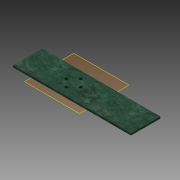
# Autodesk Inventor part: Pitch_Back
Saved by Autodesk Inventor 2013 (Build 170138000, 138)
## iProperties
Created: 2013-09-30
Part Number: Pitch_Back
Material: Generic
Document SubType Name: Modeling
Designer: Jeff
Density: 1 g/cm^3
Author: Jeff
Autodesk Inventor part; units mm, degrees
ref_plane "YZ Plane" through (0, 0, 0) normal (1, 0, 0) x (0, 1, 0)
ref_plane "XZ Plane" through (0, 0, 0) normal (0, 1, 0) x (-1, 0, 0)
ref_plane "XY Plane" through (0, 0, 0) normal (0, 0, 1) x (1, 0, 0)
ref_plane "Work Plane1" through (0, 0, 0) normal (0, 0, 1) x (1, 0, 0)
sketch "Sketch1" plane through (0, 0, 0) normal (0, 0, 1) x (1, 0, 0)
  line L0 (-37.5, -12.1467) -> (37.5, -12.1467)
  line L1 (37.5, 11.8533) -> (-37.5, 11.8533)
  line L2 (-37.5, 11.8533) -> (-37.5, -12.1467)
  line L3 (0, 0) -> (19.2852, -0.1467)
  line L4 (0, 0) -> (0, 8.1446)
  circle A0 centre (6, 0) radius 1.25
  circle A1 centre (0, 6) radius 1.25
  circle A2 centre (-6, 0) radius 1.25
  circle A3 centre (0, -6) radius 1.25
  line L5 (59.3125, -12.1467) -> (59.3125, 11.8533) projected
  line L6 (37.5, 11.8533) -> (59.3125, 11.8533)
  line L7 (59.3125, -12.1467) -> (37.5, -12.1467)
  point P0 (0, 0)
  point P1 (-37.5, 11.8533)
  dimension "d2" = 2.5
  dimension "d3" = 6
  dimension "d6" = 360
  dimension "d10" = 24
  constraints: 14 end point, 4 centre point, 4 point on line, 2 coincident, 1 horizontal, 1 parallel, 1 vertical, 15 other
  measures "d2" diameter of A0
  measures "d3" distance of point (0, 0) A0.centre
  measures "d10" distance between parallel lines of L0 L1
extrude "Extrusion1" add sketch "Sketch1" along normal blind 1.5875
body "Solid1"
